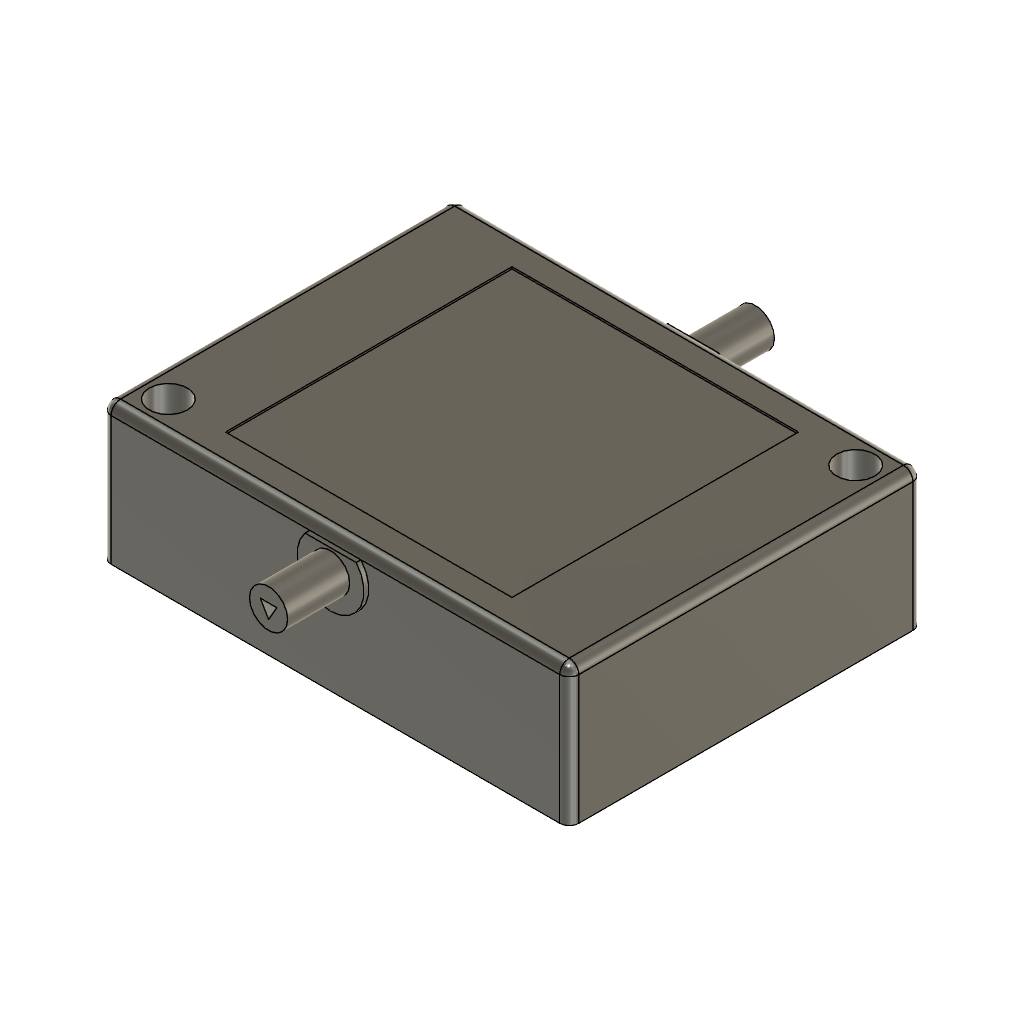
CompletedLook (Autodesk Fusion 360 archive; units mm, degrees)
design "CasePart3"
part number: 2026-10-03-21-02-19-954
Autodesk Fusion 360 part; units mm, degrees
sketch "Szkic1" plane through (0, 0, 0) normal (0, 0, 1) x (1, 0, 0)
  line L0 (0, 0) -> (49, 0)
  line L1 (49, 0) -> (49, 37)
  line L2 (49, 37) -> (0, 37)
  line L3 (0, 37) -> (0, 0)
  constraint horizontal L0
  constraint vertical L1
  constraint horizontal L2
  constraint vertical L3
  constraint coincident L0.start L3.end
extrude "Wyciągnięcie proste1" add sketch "Szkic1" along normal blind 2
sketch "Szkic2" plane through (0, 0, 0) normal (0, 0, -1) x (1, 0, 0)
  line L0 (0, 0) -> (0, -37)
  line L1 (0, -37) -> (49, -37)
  line L2 (49, -37) -> (49, 0)
  line L3 (49, 0) -> (0, 0)
  line L4 (0, 0) -> (49, 0)
  line L5 (49, 0) -> (49, -37)
  line L6 (49, -37) -> (42, -37)
  line L7 (0, -37) -> (0, 0)
  line L8 (7, -2) -> (47, -2)
  line L9 (47, -2) -> (47, -30)
  line L10 (42, -35) -> (2, -35)
  line L11 (2, -35) -> (14, -35)
  line L12 (12.5, -15) -> (2, -15)
  line L13 (2, -15) -> (2, -35)
  line L14 (47, -2) -> (35, -2)
  line L15 (36.5, -22) -> (47, -22)
  line L16 (47, -22) -> (47, -2)
  line L17 (2, -15) -> (12.5, -15)
  line L18 (13, -35) -> (2, -35)
  line L19 (2, -35) -> (2, -15)
  line L20 (47, -2) -> (36, -2)
  line L21 (36.5, -22) -> (47, -22)
  line L22 (47, -22) -> (47, -2)
  line L23 (12.5, -15) -> (12.5, -26.5)
  line L24 (36.5, -2) -> (36.5, -22)
  line L25 (0, 0) -> (7, 0)
  line L26 (7, 0) -> (7, -7)
  line L27 (7, -7) -> (0, -7)
  line L28 (0, -7) -> (0, 0)
  line L29 (2, -35) -> (2, -7)
  line L30 (49, -37) -> (42, -37)
  line L31 (42, -37) -> (42, -30)
  line L32 (42, -30) -> (49, -30)
  line L33 (49, -30) -> (49, -37)
  line L34 (19.5, -28.5) -> (19.5, -28.5)
  line L35 (19.5, -30.5) -> (19.5, -30.5)
  line L36 (12.5, -26.5) -> (12.5, -28.5)
  line L37 (12.5, -28.5) -> (12.5, -30.5)
  line L38 (12.5, -30.5) -> (19.5, -30.5)
  line L39 (29.5, -30.5) -> (35, -30.5)
  line L40 (29.5, -30.5) -> (37, -30.5)
  line L41 (2, -35) -> (21, -35)
  line L42 (49, -37) -> (42, -37)
  line L43 (19.5, -30.5) -> (19.5, -35)
  line L44 (37, -30.5) -> (38, -30.5)
  line L45 (38, -30.5) -> (38, -35)
  line L46 (29.5, -35) -> (29.5, -30.5)
  line L47 (19.5, -5.5) -> (36.5, -5.5)
  line L48 (19.5, -5.5) -> (12.5, -5.5)
  line L49 (12.5, -2) -> (13.5, -2)
  line L50 (13.5, -5.5) -> (17, -5.5)
  line L51 (18, -5.5) -> (21.5, -5.5)
  line L52 (22.5, -5.5) -> (26, -5.5)
  line L53 (27, -5.5) -> (30.5, -5.5)
  line L54 (27, -5.5) -> (30.5, -5.5)
  line L55 (31.5, -5.5) -> (35, -5.5)
  line L56 (13, -5.5) -> (12.5, -5.5)
  line L57 (30, -5.5) -> (24.5, -5.5)
  line L58 (31.5, -2) -> (31.5, -4.5)
  line L59 (30.5, -2) -> (30.5, -4.5)
  line L60 (25.5, -2) -> (25.5, -4.5)
  line L61 (24.5, -2) -> (24.5, -4.5)
  line L62 (19.5, -2) -> (19.5, -4.5)
  line L63 (18.5, -2) -> (18.5, -4.5)
  line L64 (12.5, -2) -> (12.5, -5.5)
  line L65 (13.5, -2) -> (13.5, -4.5)
  line L66 (13.5, -2) -> (15, -2)
  line L67 (13.5, -2) -> (16, -2)
  line L68 (16, -2) -> (15.5, -2)
  line L69 (16, -2) -> (16.5, -2)
  line L70 (16.5, -2) -> (16.5, -4.5)
  line L71 (15.5, -4.5) -> (15.5, -2)
  line L72 (19.5, -2) -> (21.5, -2)
  line L73 (21.5, -4.5) -> (21.5, -2)
  line L74 (22.5, -2) -> (22.5, -4.5)
  line L75 (25.5, -2) -> (27.5, -2)
  line L76 (27.5, -4.5) -> (27.5, -2)
  line L77 (28.5, -4.5) -> (28.5, -2)
  line L78 (31.5, -2) -> (33.5, -2)
  line L79 (33.5, -2) -> (33.5, -4.5)
  line L80 (34.5, -4.5) -> (34.5, -2)
  line L81 (13.5, -4.5) -> (15.5, -4.5)
  line L82 (16.5, -4.5) -> (18.5, -4.5)
  line L83 (19.5, -4.5) -> (21.5, -4.5)
  line L84 (22.5, -4.5) -> (24.5, -4.5)
  line L85 (25.5, -4.5) -> (27.5, -4.5)
  line L86 (28.5, -4.5) -> (30.5, -4.5)
  line L87 (31.5, -4.5) -> (33.5, -4.5)
  line L88 (34.5, -4.5) -> (36.5, -4.5)
  constraint horizontal L4
  constraint vertical L5
  constraint horizontal L6
  constraint vertical L7
  constraint coincident L1.end L2.start
  constraint coincident L0.start L3.end
  constraint horizontal L8
  constraint vertical L9
  constraint horizontal L10
  constraint vertical L29
  constraint horizontal L11
  constraint horizontal L12
  constraint vertical L13
  constraint horizontal L14
  constraint horizontal L15
  constraint vertical L16
  constraint horizontal L17
  constraint horizontal L18
  constraint vertical L19
  constraint coincident L11 L18.start
  constraint horizontal L20
  constraint horizontal L21
  constraint vertical L22
  constraint perpendicular L11 L23
  constraint coincident L14 L24.start
  constraint perpendicular L15 L24
  constraint horizontal L25
  constraint vertical L26
  constraint horizontal L27
  constraint vertical L28
  constraint coincident L27 L29.end
  constraint coincident L26 L8.start
  constraint horizontal L30
  constraint vertical L31
  constraint horizontal L32
  constraint vertical L33
  constraint coincident L31 L10.start
  constraint coincident L32 L9.end
  constraint horizontal L38
  constraint collinear L38 L39
  constraint coincident L10 L41.end
  constraint coincident L41 L43.end
  constraint coincident L10 L45.end
  constraint perpendicular L10 L45
  constraint coincident L10 L46.start
  constraint coincident L24 L47.end
  constraint perpendicular L24 L47
  constraint coincident L8 L49.start
  constraint coincident L8 L49.end
  constraint coincident L48 L50.start
  constraint coincident L48 L50.end
  constraint coincident L48 L51.start
  constraint coincident L47 L51.end
  constraint coincident L47 L52.start
  constraint coincident L47 L52.end
  constraint coincident L47 L53.start
  constraint coincident L47 L53.end
  constraint coincident L47 L55.start
  constraint coincident L47 L55.end
  constraint coincident L48 L56.start
  constraint coincident L53 L57.start
  constraint coincident L52 L57.end
  constraint coincident L8 L58.start
  constraint perpendicular L55 L58
  constraint coincident L8 L59.start
  constraint perpendicular L54 L59
  constraint coincident L8 L60.start
  constraint coincident L8 L61.start
  constraint perpendicular L52 L61
  constraint coincident L8 L62.start
  constraint perpendicular L8 L62
  constraint coincident L8 L63.start
  constraint perpendicular L48 L64
  constraint perpendicular L48 L65
  constraint perpendicular L63 L82
  constraint perpendicular L61 L84
  constraint perpendicular L59 L86
  constraint coincident L24 L88.end
  constraint perpendicular L24 L88
  constraint coincident L8 L66.end
  constraint perpendicular L63 L66
  constraint coincident L8 L67.end
  constraint coincident L67 L68.end
  constraint coincident L8 L69.end
  constraint perpendicular L70 L82
  constraint perpendicular L67 L71
  constraint coincident L8 L72.end
  constraint perpendicular L72 L73
  constraint coincident L8 L74.start
  constraint perpendicular L74 L84
  constraint coincident L8 L75.end
  constraint perpendicular L60 L75
  constraint perpendicular L75 L76
  constraint coincident L8 L77.end
  constraint perpendicular L8 L77
  constraint coincident L8 L78.end
  constraint perpendicular L79 L87
  constraint coincident L8 L80.end
  constraint perpendicular L8 L80
  constraint collinear L81 L82
  constraint collinear L83 L84
  constraint collinear L85 L86
  constraint collinear L87 L88
extrude "Wyciągnięcie proste2" add sketch "Szkic2" along normal blind 12.5 contours L0 L3 L4 L7 L25 L26 L27 L28 | L0 L1 L7 L10 L11 L13 L18 L19 L27 L29 L31 L41 | L2 L3 L4 L5 L8 L9 L14 L16 L20 L22 L26 L32 L49 L66 L67 L68 L69 L72 L75 L78 | L1 L2 L5 L6 L30 L31 L32 L33 L42 | L10 L11 L12 L13 L17 L18 L19 L23 L29 L36 L37 L38 L41 L43 | L8 L24 L47 L48 L49 L50 L51 L52 L53 L54 L55 L56 L57 L58 L59 L60 L61 L62 L63 L64 L65 L67 L68 L69 L70 L71 L73 L74 L76 L77 L79 L80 L81 L82 L83 L84 L85 L86 L87 L88 | L10 L39 L40 L44 L45 L46 | L8 L9 L14 L15 L16 L20 L21 L22 L24
sketch "Szkic8" plane through (0, 0, 2) normal (0, 0, 1) x (-1, 0, 0)
  line L0 (0, -37) -> (0, 0)
  line L1 (0, 0) -> (-49, 0)
  line L2 (-49, 0) -> (-49, -37)
  line L3 (-49, -37) -> (0, -37)
  line L4 (-49, -37) -> (-45.5, -37)
  line L5 (-45.5, -37) -> (-45.5, -33.5)
  line L6 (0, 0) -> (-3.5, 0)
  line L7 (-3.5, 0) -> (-3.5, -3.5)
  circle A0 centre (-3.5, -3.5) radius 2
  circle A1 centre (-45.5, -33.5) radius 2
  dimension "d17" = 4
  dimension "d18" = 4
  constraint coincident L2.end L3.start
  constraint coincident L3 L4.end
  constraint perpendicular L4 L5
  constraint coincident L0.end L1.start
  constraint coincident L1 L6.end
  constraint perpendicular L1 L7
  constraint coincident L7.end A0.centre
  constraint coincident L5.end A1.centre
  measures "d17" diameter of A0
  measures "d18" diameter of A1
extrude "Wyciągnięcie proste6" cut sketch "Szkic8" against normal blind 14 contours A0 | A1
sketch "Szkic13" plane through (0, 37, 0) normal (0, 1, 0) x (-1, 0, 0)
  line L0 (0, 2) -> (-49, 2)
  line L1 (-49, -12.5) -> (0, -12.5)
  line L2 (0, -12.5) -> (-24.5, -12.5)
  line L3 (-24.5, -12.5) -> (-24.5, -9.5)
  line L4 (-24.5, -12.5) -> (-24.5, -9.5)
  line L5 (-24.5, -9.5) -> (-28.75, -9.5)
  line L6 (-28.75, -9.5) -> (-24.5, -9.5)
  line L7 (-24.5, -9.5) -> (-20, -9.5)
  line L8 (-49, -12.5) -> (-24.5, -12.5)
  line L9 (-24.5, -9.5) -> (-29.5, -9.5)
  line L10 (-29.5, -9.5) -> (-29.5, -4.5)
  line L11 (-19.5, -9.5) -> (-19.5, -4.5)
  line L12 (-19.5, -4.5) -> (-20.25, -4.5)
  line L13 (-29.5, -4.5) -> (-20.25, -4.5)
  line L14 (-20, -9.5) -> (-19.5, -9.5)
  line L15 (0, -12.5) -> (0, 2)
  line L16 (-49, 2) -> (-49, -12.5)
  constraint midpoint L1 L2.end
  constraint perpendicular L1 L3
  constraint perpendicular L4 L5
  constraint perpendicular L4 L7
  constraint perpendicular L4 L9
  constraint perpendicular L5 L10
  constraint perpendicular L10 L13
  constraint perpendicular L11 L14
extrude "Wyciągnięcie proste11" cut sketch "Szkic13" against normal blind 2 contours L5 L6 L7 L9 L10 L11 L12 L13 L14
sketch "Szkic15" plane through (0, 0, -12) normal (0, 0, 1) x (-1, 0, 0)
  circle A0 centre (-3.5, -3.5) radius 2
  circle A1 centre (-3.5, -3.5) radius 1.5
  circle A2 centre (-45.5, -33.5) radius 1.5
  dimension "d39" = 3
  dimension "d40" = 3
  constraint concentric A0 A1
  measures "d39" diameter of A1
  measures "d40" diameter of A2
extrude "Wyciągnięcie proste13" cut sketch "Szkic15" against normal blind 1 contours A1 | A2
sketch "Szkic16" plane through (0, 37, 0) normal (0, 1, 0) x (-1, 0, 0)
  line L0 (-19.5, -4.5) -> (-19.5, -9.5)
  line L1 (-19.5, -9.5) -> (-29.5, -9.5)
  line L2 (-29.5, -9.5) -> (-29.5, -4.5)
  line L3 (-29.5, -4.5) -> (-19.5, -4.5)
  line L4 (0, 2) -> (-49, 2)
  line L5 (-49, -12.5) -> (0, -12.5)
  line L6 (-49, 2) -> (-24.5, 2)
  line L7 (-24.5, 2) -> (-24.5, -1.25)
  circle A0 centre (-24.5, -1.25) radius 2
  line L8 (0, -12.5) -> (0, 2)
  line L9 (-49, 2) -> (-49, -12.5)
  dimension "d47" = 24.5
  dimension "d48" = 3.25
  dimension "d49" = 4
  constraint perpendicular L3 L7
  constraint coincident L7.end A0.centre
  measures "d47" distance of L4.end L6.end
  measures "d48" distance of L6.end L7.end
  measures "d49" diameter of A0
extrude "Wyciągnięcie proste14" add sketch "Szkic16" along normal blind 7 contours A0
sketch "Szkic17" plane through (0, 0, 0) normal (0, -1, 0) x (1, 0, 0)
  line L0 (49, 2) -> (0, 2)
  line L1 (0, -12.5) -> (49, -12.5)
  line L2 (0, 2) -> (24.5, 2)
  line L3 (24.5, 2) -> (24.5, -1.25)
  circle A0 centre (24.5, -1.25) radius 2
  line L4 (49, -12.5) -> (49, 2)
  line L5 (0, 2) -> (0, -12.5)
  dimension "d52" = 24.5
  dimension "d53" = 3.25
  dimension "d54" = 4
  constraint perpendicular L2 L3
  constraint coincident L3.end A0.centre
  measures "d52" distance of L0.end L2.end
  measures "d53" distance of L2.end L3.end
  measures "d54" diameter of A0
extrude "Wyciągnięcie proste15" add sketch "Szkic17" along normal blind 7 contours A0
sketch "Szkic11" plane through (0, 0, 2) normal (0, 0, 1) x (-1, 0, 0)
  circle A0 centre (-3.5, -3.5) radius 2
  circle A1 centre (-45.5, -33.5) radius 2
  line L0 (0, -37) -> (0, 0)
  line L1 (0, 0) -> (-49, 0)
  line L2 (-49, 0) -> (-49, -37)
  line L3 (-49, -37) -> (0, -37)
  line L4 (0, 0) -> (-24.5, 0)
  line L5 (-24.5, 0) -> (-24.5, -3.5)
  line L6 (-9.5, -33) -> (-9.5, -33)
  line L7 (-10, -33) -> (-10, -33)
  line L8 (-9.5, -33) -> (-9.5, -33.5)
  line L9 (-9.5, -33.5) -> (-39.5, -33.5)
  line L10 (-39.5, -33.5) -> (-39.5, -3.5)
  line L11 (-39.5, -3.5) -> (-9.5, -3.5)
  line L12 (-9.5, -3.5) -> (-9.5, -33.5)
  constraint coincident L0.end L1.start
  constraint midpoint L1 L4.end
  constraint perpendicular L4 L5
  constraint horizontal L9
  constraint vertical L10
  constraint horizontal L11
  constraint vertical L12
  constraint coincident L11 L5.end
extrude "Wyciągnięcie proste9" cut sketch "Szkic11" against normal blind 0.2 contours L8 L9 L10 L11 L12
sketch "Szkic18" plane through (0, 44, 0) normal (0, 1, 0) x (-1, 0, 0)
  circle A0 centre (-24.5, -1.25) radius 2
  circle A1 centre (-24.5, -1.25) radius 2
  circle A2 centre (-24.5, -1.25) radius 1
  line L0 (-24.5, -1.25) -> (-24.5, -2.25)
  line L1 (-24.5, -2.25) -> (-25.3652, -0.7485)
  line L2 (-24.5, -2.25) -> (-23.6348, -0.7485)
  line L3 (-25.3652, -0.7485) -> (-23.6348, -0.7485)
  dimension "d57" = 2
  constraint concentric A0 A1
  constraint concentric A1 A2
  constraint coincident A0.centre A1.centre
  constraint coincident A2 L0.end
  constraint vertical L0
  constraint coincident A2 L1.end
  constraint coincident A2 L2.end
  constraint horizontal L3
  measures "d57" diameter of A2
extrude "Wyciągnięcie proste16" cut sketch "Szkic18" against normal blind 3 contours L1 L2 L3
sketch "Szkic19" plane through (0, -7, 0) normal (0, -1, 0) x (1, 0, 0)
  circle A0 centre (24.5, -1.25) radius 2
  circle A1 centre (24.5, -1.25) radius 2
  circle A2 centre (24.5, -1.25) radius 1
  line L0 (24.5, -1.25) -> (24.5, -2.25)
  line L1 (24.5, -2.25) -> (25.366, -0.7499)
  line L2 (24.5, -2.25) -> (23.634, -0.7499)
  line L3 (23.634, -0.7499) -> (25.366, -0.7499)
  dimension "d60" = 2
  constraint concentric A0 A1
  constraint concentric A1 A2
  constraint coincident A0.centre A1.centre
  constraint coincident A2 L0.end
  constraint vertical L0
  constraint coincident A2 L1.end
  constraint coincident A2 L2.end
  constraint horizontal L3
  measures "d60" diameter of A2
extrude "Wyciągnięcie proste17" cut sketch "Szkic19" against normal blind 3 contours L1 L2 L3
fillet "Zaokrąglenie2" radius 1 8 edges at (0, 37, -5.25) (0, 0, -5.25) (0, 18.5, 2) (24.5, 37, 2) (49, 37, -5.25) (49, 18.5, 2) (24.5, 0, 2) (49, 0, -5.25)
sketch "Szkic20" plane through (0, 0, 0) normal (0, -1, 0) x (1, 0, 0)
  line L0 (48, -12.5) -> (48, 1)
  line L1 (48, 1) -> (1, 1)
  line L2 (1, 1) -> (1, -12.5)
  line L3 (1, -12.5) -> (48, -12.5)
  circle A0 centre (24.5, -1.25) radius 2
  circle A1 centre (24.5, -1.25) radius 3.5
  dimension "d66" = 7
  measures "d66" diameter of A1
extrude "Wyciągnięcie proste18" add sketch "Szkic20" along normal blind 0.5 contours L1 A1 picked at (22.0612, 0.4859)
sketch "Szkic21" plane through (0, 37, 0) normal (0, 1, 0) x (-1, 0, 0)
  line L0 (-48, 1) -> (-48, -12.5)
  line L1 (-48, -12.5) -> (-1, -12.5)
  line L2 (-1, -12.5) -> (-1, 1)
  line L3 (-1, 1) -> (-48, 1)
  circle A0 centre (-24.5, -1.25) radius 2
  line L4 (-19.5, -4.5) -> (-19.5, -9.5)
  line L5 (-19.5, -9.5) -> (-29.5, -9.5)
  line L6 (-29.5, -9.5) -> (-29.5, -4.5)
  line L7 (-29.5, -4.5) -> (-19.5, -4.5)
  circle A1 centre (-24.5, -1.25) radius 3.5
  dimension "d69" = 7
  constraint concentric A0 A1
  measures "d69" diameter of A1
extrude "Wyciągnięcie proste19" add sketch "Szkic21" along normal blind 0.5 contours L3 L7 A1
equation "d47 = ( 49.000 / 2 ) * 1 mm"
equation "d48 = ( 6.500 / 2 ) * 1 mm"
equation "d52 = ( 49.000 / 2 ) * 1 mm"

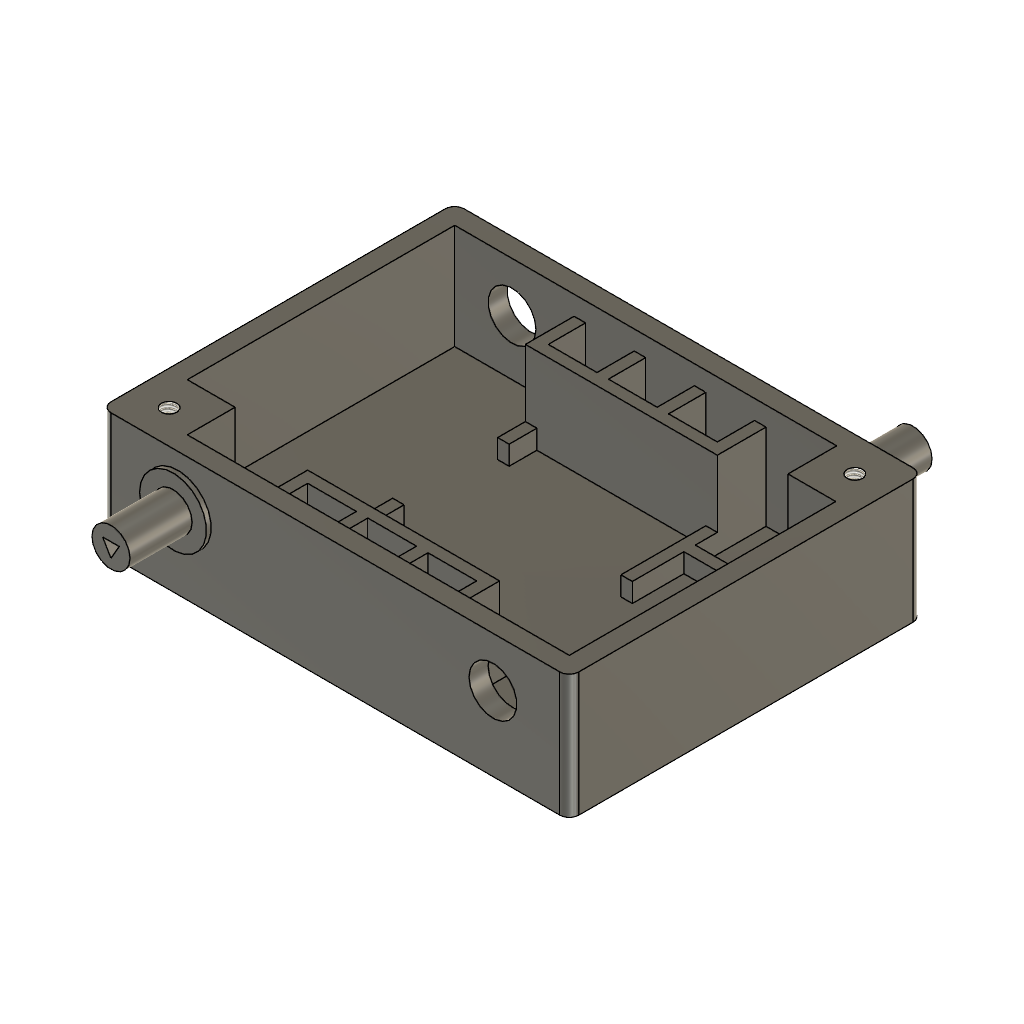
design "CasePart1"
part number: 2026-10-03-18-17-18-057
Autodesk Fusion 360 part; units mm, degrees
sketch "Szkic1" plane through (0, 0, 0) normal (0, 0, 1) x (1, 0, 0)
  line L0 (0, 0) -> (49, 0)
  line L1 (49, 0) -> (49, 37)
  line L2 (49, 37) -> (0, 37)
  line L3 (0, 37) -> (0, 0)
  constraint horizontal L0
  constraint vertical L1
  constraint horizontal L2
  constraint vertical L3
  constraint coincident L0.start L3.end
extrude "Wyciągnięcie proste1" add sketch "Szkic1" along normal blind 2
sketch "Szkic2" plane through (0, 0, 2) normal (0, 0, 1) x (-1, 0, 0)
  line L0 (0, -37) -> (0, 0)
  line L1 (0, 0) -> (-49, 0)
  line L2 (-49, 0) -> (-49, -37)
  line L3 (-49, -37) -> (0, -37)
  line L4 (0, -37) -> (-2, -37)
  line L5 (-2, 0) -> (0, 0)
  line L6 (0, 0) -> (0, -37)
  line L7 (-14.5, -2) -> (-47, -2)
  line L8 (-49, -2) -> (-49, 0)
  line L9 (-49, 0) -> (-2, 0)
  line L10 (-49, -2) -> (-49, -37)
  line L11 (-49, -37) -> (-47, -37)
  line L12 (-47, -29.9) -> (-47, -2)
  line L13 (-2, -37) -> (-47, -37)
  line L14 (-34.5, -35) -> (-2, -35)
  line L15 (-2, -35) -> (-2, -7.1)
  line L16 (-47, -29.9) -> (-42, -29.9)
  line L17 (-34.5, -29.9) -> (-34.5, -30)
  line L18 (-7, -2) -> (-7, -7)
  line L19 (-7, -7) -> (-2, -7)
  line L20 (-2, -7) -> (-2, -7.1)
  line L21 (-14.5, -2) -> (-7, -2)
  line L22 (-42, -35) -> (-42, -29.9)
  line L23 (-42, -35) -> (-34.5, -35)
  constraint horizontal L4
  constraint vertical L15
  constraint horizontal L5
  constraint vertical L6
  constraint coincident L1 L5.start
  constraint coincident L0.start L3.end
  constraint horizontal L7
  constraint vertical L8
  constraint horizontal L9
  constraint coincident L1.end L2.start
  constraint vertical L10
  constraint horizontal L11
  constraint vertical L12
  constraint coincident L2.end L3.start
  constraint horizontal L13
  constraint horizontal L14
  constraint horizontal L16
  constraint vertical L17
  constraint perpendicular L18 L19
  constraint parallel L1 L21
  constraint perpendicular L16 L22
extrude "Wyciągnięcie proste2" add sketch "Szkic2" along normal blind 11
sketch "Szkic3" plane through (0, 0, 2) normal (0, 0, 1) x (-1, 0, 0)
  line L0 (-2, -35) -> (-2, -7.1)
  line L1 (-14.5, -2) -> (-47, -2)
  line L2 (-47, -2) -> (-47, -29.9)
  line L3 (-42, -35) -> (-2, -35)
  line L4 (-10, -10.6) -> (-2, -10.6)
  line L5 (-14.5, -27) -> (-14.5, -35)
  line L6 (-10, -10.6) -> (-14.5, -10.6)
  line L7 (-14.5, -10.6) -> (-14.5, -16)
  line L8 (-14.5, -9.4) -> (-14.5, -2)
  line L9 (-13.8092, -9.4) -> (-14.5, -9.4)
  line L10 (-13.8092, -9.4) -> (-2, -9.4)
  line L11 (-15.7, -35) -> (-15.7, -31.1)
  line L12 (-20, -31.1) -> (-15.7, -31.1)
  line L13 (-20, -29.9) -> (-15.7, -29.9)
  line L14 (-15.7, -27) -> (-15.7, -29.9)
  line L15 (-15.7, -31.1) -> (-15.7, -35)
  line L16 (-20, -29.9) -> (-33.4, -29.9)
  line L17 (-34.5, -29.9) -> (-42, -29.9)
  line L18 (-34.6, -33.7358) -> (-34.6, -35)
  line L19 (-34.6, -35) -> (-33.4, -35)
  line L20 (-33.4, -35) -> (-33.4, -31.1)
  line L21 (-34.6, -33.7358) -> (-34.6, -31.1)
  line L22 (-34.6, -31.1) -> (-34.6, -29.9)
  line L23 (-47, -27.6) -> (-47, -26.4)
  line L24 (-47, -29.9) -> (-47, -27.6)
  line L25 (-47, -27.6) -> (-47, -26.4)
  line L26 (-43.1782, -26.4) -> (-47, -26.4)
  line L27 (-47, -27.6) -> (-42.2525, -27.6)
  line L28 (-42.2525, -26.4) -> (-43.1782, -26.4)
  line L29 (-33.4, -2) -> (-34.6, -2)
  line L30 (-34.6, -27.6) -> (-42.2525, -27.6)
  line L31 (-42.2525, -26.4) -> (-34.6, -26.4)
  line L32 (-20, -31.1) -> (-33.4, -31.1)
  line L33 (-34.6, -30.1881) -> (-34.6, -27.6)
  line L34 (-18.5, -5.9) -> (-15.7, -5.9)
  line L35 (-20, -7.1) -> (-15.7, -7.1)
  line L36 (-20, -7.1) -> (-33.4, -7.1)
  line L37 (-18.5, -5.9) -> (-33.4, -5.9)
  line L38 (-15.7, -16) -> (-15.7, -7.1)
  line L39 (-15.7, -5.9) -> (-15.7, -2)
  line L40 (-33.4, -5.9) -> (-33.4, -2)
  line L41 (-14.5, -2) -> (-15.7, -2)
  line L42 (-33.4, -21) -> (-34.6, -21)
  line L43 (-33.4, -10) -> (-34.6, -10)
  line L44 (-33.4, -2) -> (-33.4, -5.9)
  line L45 (-33.4, -7.1) -> (-33.4, -10)
  line L46 (-33.4, -35) -> (-33.4, -31.1)
  line L47 (-33.4, -29.9) -> (-33.4, -21)
  line L48 (-15.7, -16) -> (-14.5, -16)
  line L49 (-15.7, -2) -> (-15.7, -5.9)
  line L50 (-15.7, -7.1) -> (-15.7, -16)
  line L51 (-14.5, -35) -> (-14.5, -27)
  line L52 (-14.5, -35) -> (-14.5, -27)
  line L53 (-15.7, -27) -> (-14.5, -27)
  line L54 (-34.6, -26.4) -> (-34.6, -21)
  line L55 (-34.6, -10) -> (-34.6, -2)
  line L56 (-33.4, -29.9) -> (-33.4, -21)
  line L57 (-33.4, -10) -> (-33.4, -7.1)
  line L58 (-47, -29.9) -> (-42, -29.9)
  line L59 (-42, -29.9) -> (-42, -35)
  line L60 (-2, -7.1) -> (-2, -7)
  line L61 (-2, -7) -> (-7, -7)
  line L62 (-7, -7) -> (-7, -2)
  line L63 (-7, -2) -> (-14.5, -2)
  line L64 (-15.7, -29.9) -> (-14.5, -29.9)
  line L65 (-34.6, -29.9) -> (-33.4, -29.9)
  line L66 (-15.7, -7.1) -> (-14.5, -7.1)
  line L67 (-33.4, -7.1) -> (-34.6, -7.1)
  constraint coincident L0 L4.end
  constraint perpendicular L0 L4
  constraint coincident L3 L5.end
  constraint perpendicular L3 L5
  constraint coincident L3 L11.start
  constraint perpendicular L3 L15
  constraint coincident L1 L39.end
  constraint perpendicular L1 L39
  constraint coincident L1 L8.end
  constraint perpendicular L1 L8
  constraint perpendicular L8 L9
  constraint coincident L0 L10.end
  constraint perpendicular L0 L10
  constraint perpendicular L11 L12
  constraint perpendicular L13 L14
  constraint collinear L14 L15
  constraint coincident L3 L18.end
  constraint perpendicular L3 L18
  constraint coincident L3 L19.end
  constraint perpendicular L20 L32
  constraint perpendicular L16 L22
  constraint coincident L2 L23.start
  constraint coincident L2 L23.end
  constraint coincident L2.end L24.start
  constraint perpendicular L25 L26
  constraint perpendicular L23 L27
  constraint coincident L1 L29.start
  constraint perpendicular L1 L40
  constraint coincident L22 L33.start
  constraint coincident L1 L29.end
  constraint perpendicular L1 L55
  constraint perpendicular L31 L54
  constraint collinear L33 L54
  constraint perpendicular L34 L39
  constraint perpendicular L35 L38
  constraint perpendicular L36 L57
  constraint perpendicular L37 L40
  constraint collinear L38 L39
  constraint collinear L40 L57
  constraint perpendicular L3 L46
  constraint perpendicular L42 L56
  constraint perpendicular L43 L55
  constraint collinear L44 L45
  constraint collinear L46 L47
  constraint perpendicular L7 L48
  constraint collinear L49 L50
  constraint perpendicular L5 L53
  constraint collinear L54 L55
  constraint collinear L56 L57
  constraint coincident L51 L64.end
  constraint perpendicular L51 L64
  constraint perpendicular L56 L65
  constraint coincident L8 L66.end
  constraint perpendicular L8 L66
  constraint coincident L55 L67.end
  constraint perpendicular L55 L67
extrude "Wyciągnięcie proste3" add sketch "Szkic3" along normal blind 2 contours L0 L4 L6 L7 L8 L9 L10 L38 L48 L50 L66 | L3 L5 L11 L12 L13 L15 L16 L17 L18 L19 L20 L21 L22 L32 L33 L46 L51 L52 L64 L65 | L5 L14 L51 L52 L53 L64 | L1 L8 L29 L34 L35 L36 L37 L39 L40 L41 L44 L49 L55 L66 L67 | L2 L17 L23 L25 L26 L27 L28 L30 L31 L33 L42 L47 L54 L56 L65 | L43 L45 L55 L57 L67
sketch "Szkic4" plane through (0, 0, 4) normal (0, 0, 1) x (-1, 0, 0)
  line L0 (-15.7, -29.9) -> (-33.4, -29.9)
  line L1 (-33.4, -29.9) -> (-33.4, -21)
  line L2 (-33.4, -21) -> (-34.6, -21)
  line L3 (-34.6, -21) -> (-34.6, -26.4)
  line L4 (-34.6, -26.4) -> (-47, -26.4)
  line L5 (-47, -26.4) -> (-47, -27.6)
  line L6 (-47, -27.6) -> (-34.6, -27.6)
  line L7 (-34.6, -27.6) -> (-34.6, -35)
  line L8 (-34.6, -35) -> (-33.4, -35)
  line L9 (-33.4, -35) -> (-33.4, -31.1)
  line L10 (-33.4, -31.1) -> (-15.7, -31.1)
  line L11 (-15.7, -31.1) -> (-15.7, -35)
  line L12 (-15.7, -35) -> (-14.5, -35)
  line L13 (-14.5, -35) -> (-14.5, -27)
  line L14 (-14.5, -27) -> (-15.7, -27)
  line L15 (-15.7, -27) -> (-15.7, -29.9)
  line L16 (-14.5, -35) -> (-15.7, -35)
  line L17 (-15.7, -35) -> (-15.7, -31.1)
  line L18 (-15.7, -29.9) -> (-14.5, -29.9)
  line L19 (-14.5, -29.9) -> (-14.5, -35)
  line L20 (-15.7, -29.9) -> (-34.6, -29.9)
  line L21 (-34.6, -29.9) -> (-34.6, -31.1)
  line L22 (-33.4, -31.1) -> (-15.7, -31.1)
  line L23 (-33.4, -31.1) -> (-33.4, -35)
  line L24 (-33.4, -35) -> (-34.6, -35)
  line L25 (-34.6, -35) -> (-34.6, -31.1)
  line L26 (-15.7, -31.1) -> (-20, -31.1)
  line L27 (-33.4, -31.1) -> (-29, -31.1)
  line L28 (-33.4, -31.1) -> (-28.3, -31.1)
  line L29 (-28.3, -31.1) -> (-28.3, -35)
  line L30 (-28.3, -35) -> (-27.1, -35)
  line L31 (-27.1, -35) -> (-27.1, -31.1)
  line L32 (-27.1, -31.1) -> (-22, -31.1)
  line L33 (-22, -31.1) -> (-22, -35)
  line L34 (-22, -35) -> (-20.8, -35)
  line L35 (-20.8, -35) -> (-20.8, -31.1)
  dimension "d67" = 5.1
  dimension "d68" = 1.2
  dimension "d69" = 5.1
  dimension "d70" = 1.2
  constraint horizontal L16
  constraint vertical L17
  constraint horizontal L18
  constraint vertical L19
  constraint coincident L0.start L15.end
  constraint coincident L12.end L13.start
  constraint horizontal L20
  constraint vertical L21
  constraint horizontal L22
  constraint coincident L7 L21.end
  constraint vertical L23
  constraint horizontal L24
  constraint vertical L25
  constraint coincident L8.end L9.start
  constraint coincident L22 L26.end
  constraint coincident L9.end L10.start
  constraint coincident L22 L27.end
  constraint perpendicular L11 L28
  constraint perpendicular L28 L29
  constraint perpendicular L29 L30
  constraint coincident L22 L31.end
  constraint perpendicular L22 L31
  constraint perpendicular L31 L32
  constraint perpendicular L10 L33
  constraint perpendicular L33 L34
  constraint coincident L22 L35.end
  constraint perpendicular L22 L35
  measures "d67" distance of L9.end L28.end
  measures "d68" distance of L29.end L30.end
  measures "d69" distance of L31.end L32.end
  measures "d70" distance of L33.end L34.end
extrude "Wyciągnięcie proste4" add sketch "Szkic4" along normal blind 7 contours L0 L7 L8 L9 L10 L11 L12 L13 L16 L17 L18 L19 L20 L21 L22 L23 L24 L25 L26 L27 L28 L32 | L10 L22 L33 L34 L35 | L10 L22 L29 L30 L31
sketch "Szkic5" plane through (0, 0, 4) normal (0, 0, 1) x (-1, 0, 0)
  line L0 (-34.6, -10) -> (-33.4, -10)
  line L1 (-33.4, -10) -> (-33.4, -7.1)
  line L2 (-33.4, -7.1) -> (-15.7, -7.1)
  line L3 (-15.7, -7.1) -> (-15.7, -16)
  line L4 (-15.7, -16) -> (-14.5, -16)
  line L5 (-14.5, -16) -> (-14.5, -10.6)
  line L6 (-14.5, -10.6) -> (-2, -10.6)
  line L7 (-2, -10.6) -> (-2, -9.4)
  line L8 (-2, -9.4) -> (-14.5, -9.4)
  line L9 (-14.5, -9.4) -> (-14.5, -2)
  line L10 (-14.5, -2) -> (-15.7, -2)
  line L11 (-15.7, -2) -> (-15.7, -5.9)
  line L12 (-15.7, -5.9) -> (-33.4, -5.9)
  line L13 (-33.4, -5.9) -> (-33.4, -2)
  line L14 (-33.4, -2) -> (-34.6, -2)
  line L15 (-34.6, -2) -> (-34.6, -10)
  line L16 (-34.6, -2) -> (-33.4, -2)
  line L17 (-33.4, -2) -> (-33.4, -5.9)
  line L18 (-33.4, -7.1) -> (-34.6, -7.1)
  line L19 (-34.6, -7.1) -> (-34.6, -2)
  line L20 (-33.4, -7.1) -> (-14.5, -7.1)
  line L21 (-14.5, -7.1) -> (-14.5, -5.9)
  line L22 (-15.7, -5.9) -> (-15.7, -2)
  line L23 (-15.7, -2) -> (-14.5, -2)
  line L24 (-14.5, -2) -> (-14.5, -5.9)
  line L25 (-33.4, -5.9) -> (-28.3, -5.9)
  line L26 (-28.3, -5.9) -> (-28.3, -2)
  line L27 (-28.3, -2) -> (-27.1, -2)
  line L28 (-27.1, -2) -> (-27.1, -5.9)
  line L29 (-27.1, -5.9) -> (-22, -5.9)
  line L30 (-22, -5.9) -> (-22, -2)
  line L31 (-22, -2) -> (-20.8, -2)
  line L32 (-20.8, -2) -> (-20.8, -5.9)
  line L33 (-33.4, -5.9) -> (-28.3, -5.9)
  line L34 (-27.1, -5.9) -> (-22, -5.9)
  line L35 (-20.8, -5.9) -> (-15.7, -5.9)
  line L36 (-33.4, -7.1) -> (-14.5, -7.1)
  dimension "d71" = 5.1
  dimension "d72" = 1.2
  dimension "d73" = 5.1
  dimension "d74" = 1.2
  constraint horizontal L16
  constraint vertical L17
  constraint horizontal L18
  constraint vertical L19
  constraint coincident L1.end L2.start
  constraint coincident L14.end L15.start
  constraint horizontal L20
  constraint vertical L21
  constraint coincident L9 L21.end
  constraint vertical L22
  constraint horizontal L23
  constraint vertical L24
  constraint coincident L10.end L11.start
  constraint coincident L12.end L13.start
  constraint perpendicular L22 L35
  constraint perpendicular L13 L25
  constraint perpendicular L12 L26
  constraint perpendicular L26 L27
  constraint coincident L12 L28.end
  constraint perpendicular L12 L28
  constraint perpendicular L28 L29
  constraint perpendicular L12 L30
  constraint perpendicular L30 L31
  constraint coincident L12 L32.end
  constraint perpendicular L12 L32
  constraint collinear L33 L34
  constraint collinear L34 L35
  measures "d71" distance of L12.end L25.end
  measures "d72" distance of L26.end L27.end
  measures "d73" distance of L28.end L29.end
  measures "d74" distance of L30.end L31.end
extrude "Wyciągnięcie proste5" add sketch "Szkic5" along normal blind 7 contours L2 L9 L10 L11 L12 L13 L14 L15 L16 L17 L18 L19 L20 L21 L22 L23 L24 L25 L29 L33 L34 L35 L36 | L12 L26 L27 L28 | L12 L30 L31 L32
sketch "Szkic12" plane through (0, 0, 0) normal (0, -1, 0) x (1, 0, 0)
  line L0 (0, 0) -> (49, 0)
  line L1 (49, 0) -> (49, 13)
  line L2 (49, 13) -> (0, 13)
  line L3 (0, 13) -> (0, 0)
  line L4 (0, 0) -> (8, 0)
  line L5 (8, 0) -> (8, 7.8)
  circle A0 centre (8, 7.8) radius 2
  dimension "d27" = 8
  dimension "d28" = 7.8
  dimension "d62" = 4
  constraint coincident L0.start L3.end
  constraint perpendicular L3 L4
  constraint perpendicular L4 L5
  constraint coincident L5.end A0.centre
  measures "d27" distance of L0.start L4.end
  measures "d28" distance of L4.end L5.end
  measures "d62" diameter of A0
extrude "Wyciągnięcie proste8" add sketch "Szkic12" along normal blind 7 contours A0
sketch "Szkic13" plane through (0, 0, 0) normal (0, -1, 0) x (1, 0, 0)
  line L0 (0, 0) -> (49, 0)
  line L1 (49, 0) -> (49, 13)
  line L2 (49, 13) -> (0, 13)
  line L3 (0, 13) -> (0, 0)
  line L4 (49, 0) -> (41, 0)
  line L5 (41, 0) -> (41, 7.8)
  circle A0 centre (41, 7.8) radius 2.5
  circle A1 centre (8, 7.8) radius 2
  dimension "d54" = 8
  dimension "d55" = 7.8
  dimension "d56" = 5
  constraint coincident L0.end L1.start
  constraint perpendicular L1 L4
  constraint perpendicular L0 L5
  constraint coincident L5.end A0.centre
  measures "d54" distance of L0.end L4.end
  measures "d55" distance of L4.end L5.end
  measures "d56" diameter of A0
extrude "Wyciągnięcie proste9" cut sketch "Szkic13" against normal blind 2 contours A0
sketch "Szkic14" plane through (0, 37, 0) normal (0, 1, 0) x (-1, 0, 0)
  line L0 (-49, 0) -> (0, 0)
  line L1 (0, 0) -> (0, 13)
  line L2 (0, 13) -> (-49, 13)
  line L3 (-49, 13) -> (-49, 0)
  line L4 (-49, 0) -> (-41, 0)
  line L5 (-41, 0) -> (-41, 7.8)
  circle A0 centre (-41, 7.8) radius 2
  dimension "d57" = 8
  dimension "d58" = 7.8
  dimension "d61" = 4
  constraint coincident L0.start L3.end
  constraint perpendicular L3 L4
  constraint perpendicular L0 L5
  measures "d57" distance of L0.start L4.end
  measures "d58" distance of L4.end L5.end
  measures "d61" diameter of A0
extrude "Wyciągnięcie proste10" add sketch "Szkic14" along normal blind 7 contours A0
sketch "Szkic15" plane through (0, 37, 0) normal (0, 1, 0) x (-1, 0, 0)
  line L0 (-49, 0) -> (0, 0)
  line L1 (0, 0) -> (0, 13)
  line L2 (0, 13) -> (-49, 13)
  line L3 (-49, 13) -> (-49, 0)
  line L4 (0, 0) -> (-8, 0)
  line L5 (-8, 0) -> (-8, 7.8)
  circle A0 centre (-8, 7.8) radius 2.5
  circle A1 centre (-41, 7.8) radius 2
  dimension "d42" = 8
  dimension "d43" = 7.8
  dimension "d44" = 5
  constraint coincident L0.end L1.start
  constraint perpendicular L1 L4
  constraint perpendicular L4 L5
  constraint coincident L5.end A0.centre
  measures "d42" distance of L0.end L4.end
  measures "d43" distance of L4.end L5.end
  measures "d44" diameter of A0
extrude "Wyciągnięcie proste11" cut sketch "Szkic15" against normal blind 2 contours A0
sketch "Szkic16" plane through (0, 0, 13) normal (0, 0, 1) x (-1, 0, 0)
  line L0 (-42, -29.9) -> (-47, -29.9)
  line L1 (-47, -29.9) -> (-47, -2)
  line L2 (-14.5, -2) -> (-7, -2)
  line L3 (-7, -2) -> (-7, -7)
  line L4 (-7, -7) -> (-2, -7)
  line L5 (-2, -7) -> (-2, -7.1)
  line L6 (-2, -7.1) -> (-2, -35)
  line L7 (-2, -35) -> (-42, -35)
  line L8 (-42, -35) -> (-42, -29.9)
  line L9 (-49, 0) -> (-49, -37)
  line L10 (-49, -37) -> (0, -37)
  line L11 (0, -37) -> (0, 0)
  line L12 (0, 0) -> (-49, 0)
  line L13 (0, 0) -> (-3.5928, 0)
  line L14 (-3.5928, 0) -> (-3.5928, -3.5)
  line L15 (-3.5928, -3.5) -> (0, -3.5)
  line L16 (0, -3.5) -> (0, 0)
  line L17 (-49, -37) -> (-45.5, -37)
  line L18 (-45.5, -37) -> (-45.5, -33.4072)
  line L19 (-45.5, -33.4072) -> (-49, -33.4072)
  line L20 (-49, -33.4072) -> (-49, -37)
  line L21 (-47, -2) -> (-14.5, -2)
  constraint horizontal L13
  constraint vertical L14
  constraint horizontal L15
  constraint vertical L16
  constraint coincident L11.end L12.start
  constraint horizontal L17
  constraint vertical L18
  constraint horizontal L19
  constraint vertical L20
  constraint coincident L9.end L10.start
hole "Otwór1" at (45.5, 33.4072, 13) at (3.5928, 3.5, 13) direction (0, 0, -1) diameter 1.623 depth 8 tip angle 118
thread "Gwint1" "ISO Metric profile 2.0 M2x0.4 M2x0.4 6H" major diameter 2.074 minor diameter 1.623 pitch 0.4 angle 60 resizes the face on face at (44.6888, 33.4275, 10.3333) on face at (3.6736, 2.6925, 10.3333)
fillet "Zaokrąglenie1" radius 1 4 edges at (0, 0, 6.5) (49, 0, 6.5) (0, 37, 6.5) (49, 37, 6.5)
sketch "Szkic17" plane through (0, 44, 0) normal (0, 1, 0) x (-1, 0, 0)
  circle A0 centre (-41, 7.8) radius 2
  circle A1 centre (-41, 7.8) radius 2
  circle A2 centre (-41, 7.8) radius 1
  line L0 (-41, 6.8) -> (-40.1339, 8.2998)
  line L1 (-41, 6.8) -> (-41.8661, 8.2998)
  line L2 (-41.8661, 8.2998) -> (-40.1339, 8.2998)
  constraint concentric A0 A1
  constraint concentric A1 A2
  constraint coincident A2 L0.start
  constraint coincident A2 L0.end
  constraint coincident A2 L1.end
  constraint horizontal L2
extrude "Wyciągnięcie proste12" cut sketch "Szkic17" against normal blind 3 contours L0 L1 L2
sketch "Szkic18" plane through (0, -7, 0) normal (0, -1, 0) x (1, 0, 0)
  circle A0 centre (8, 7.8) radius 2
  circle A1 centre (8, 7.8) radius 2
  circle A2 centre (8, 7.8) radius 1
  line L0 (8, 6.8) -> (8.8661, 8.2999)
  line L1 (8, 6.8) -> (7.1339, 8.2999)
  line L2 (7.1339, 8.2999) -> (8.8661, 8.2999)
  dimension "d77" = 2
  constraint concentric A0 A1
  constraint concentric A1 A2
  constraint coincident A2 L0.start
  constraint coincident A2 L0.end
  constraint coincident A2 L1.end
  constraint horizontal L2
  measures "d77" diameter of A2
extrude "Wyciągnięcie proste13" cut sketch "Szkic18" against normal blind 3 contours L0 L1 L2
sketch "Szkic19" plane through (0, 0, 0) normal (0, -1, 0) x (1, 0, 0)
  circle A0 centre (8, 7.8) radius 2
  circle A1 centre (41, 7.8) radius 2.5
  line L0 (48, 0) -> (48, 13)
  line L1 (48, 13) -> (1, 13)
  line L2 (1, 13) -> (1, 0)
  line L3 (1, 0) -> (48, 0)
  circle A2 centre (8, 7.8) radius 3.5
  dimension "d80" = 7
  constraint concentric A0 A2
  measures "d80" diameter of A2
extrude "Wyciągnięcie proste14" add sketch "Szkic19" along normal blind 0.5 contours A2
sketch "Szkic20" plane through (0, 37, 0) normal (0, 1, 0) x (-1, 0, 0)
  circle A0 centre (-8, 7.8) radius 2.5
  circle A1 centre (-41, 7.8) radius 2
  line L0 (-48, 13) -> (-48, 0)
  line L1 (-48, 0) -> (-1, 0)
  line L2 (-1, 0) -> (-1, 13)
  line L3 (-1, 13) -> (-48, 13)
  circle A2 centre (-41, 7.8) radius 3.5
  dimension "d83" = 7
  constraint concentric A1 A2
  measures "d83" diameter of A2
extrude "Wyciągnięcie proste15" add sketch "Szkic20" along normal blind 0.5 contours A2

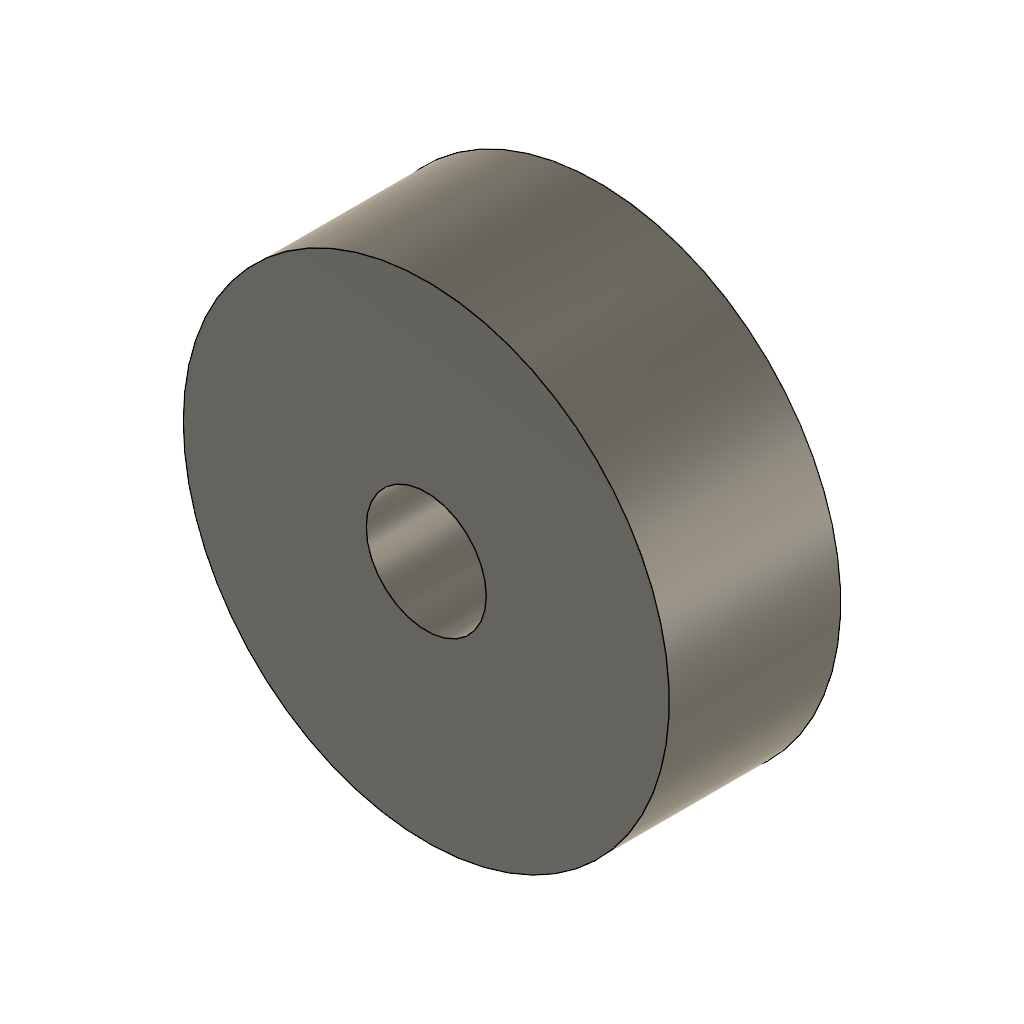
design "WheelType2"
part number: 2026-10-04-14-52-17-091
Autodesk Fusion 360 part; units mm, degrees
sketch "Szkic1" plane through (0, 0, 0) normal (0, 1, 0) x (1, 0, 0)
  circle A0 centre (0, 0) radius 2.1
  circle A1 centre (0, 0) radius 8.5
  dimension "d7" = 4.2
  dimension "d10" = 17
  measures "d7" diameter of A0
  measures "d10" diameter of A1
extrude "Wyciągnięcie proste1" add sketch "Szkic1" along normal blind 6

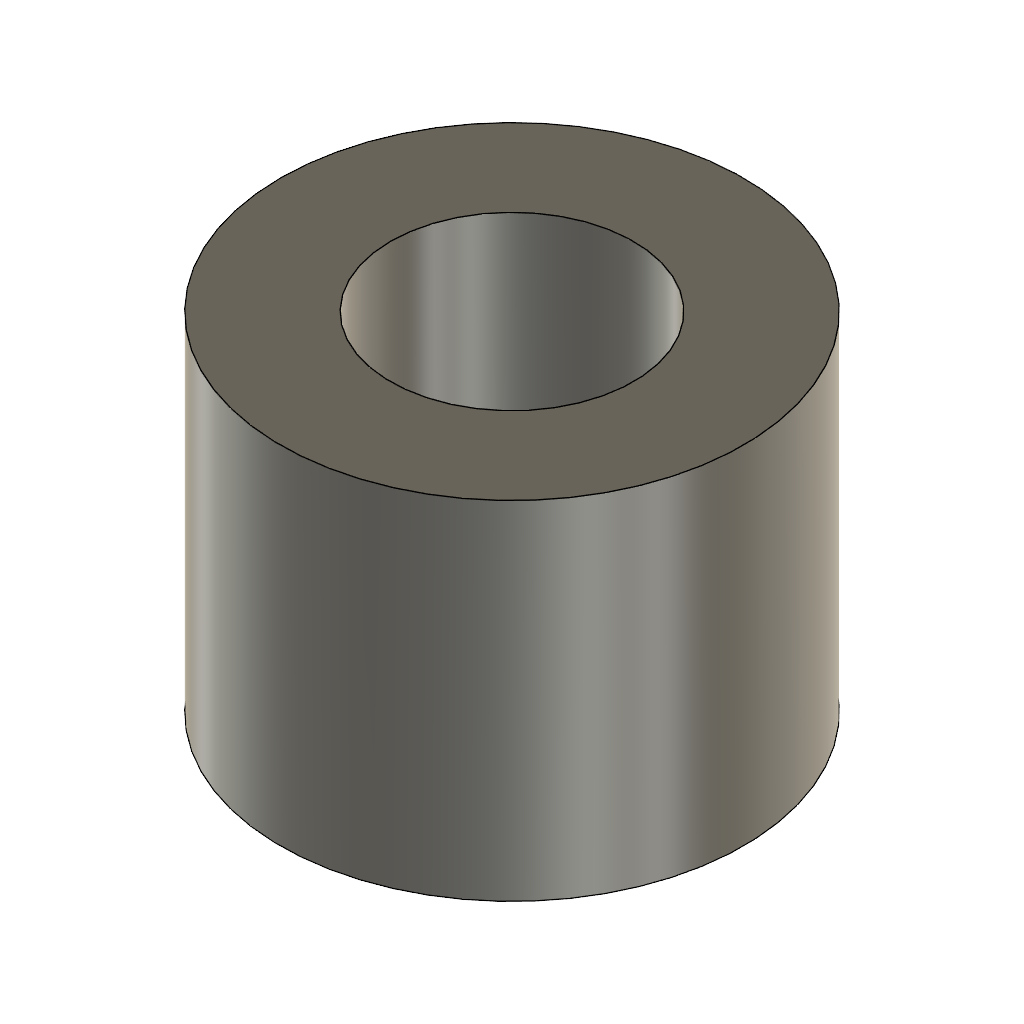
design "TensionWheel"
part number: 2026-10-11-19-17-43-800
Autodesk Fusion 360 part; units mm, degrees
sketch "Szkic1" plane through (0, 0, 0) normal (0, 0, 1) x (1, 0, 0)
  circle A0 centre (0, 0) radius 2.1
  circle A1 centre (0, 0) radius 4
  dimension "d1" = 4.2
  dimension "d5" = 8
  constraint coincident A0.centre A1.centre
  measures "d1" diameter of A0
  measures "d5" diameter of A1
extrude "Wyciągnięcie proste1" add sketch "Szkic1" along normal blind 6

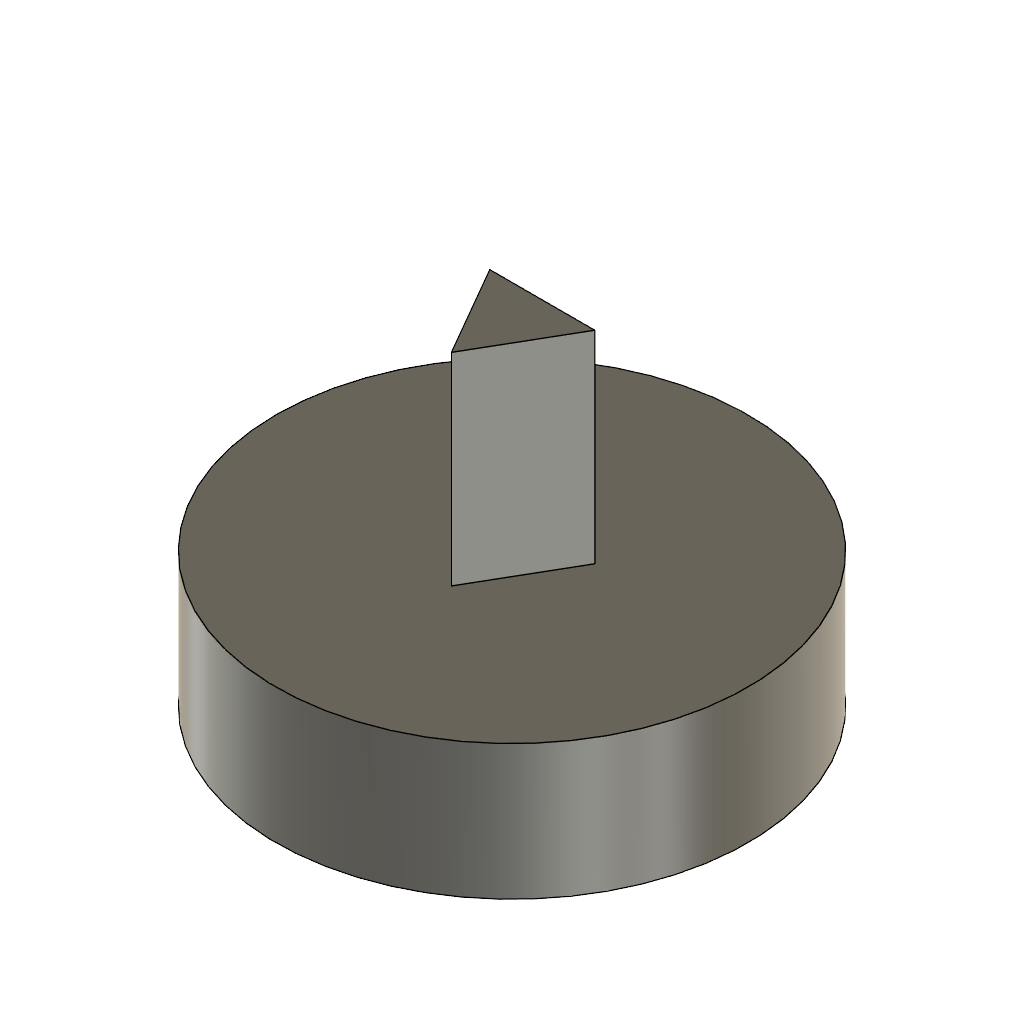
design "WheelCap"
part number: 2026-10-10-16-35-32-340
Autodesk Fusion 360 part; units mm, degrees
sketch "Szkic1" plane through (0, 0, 0) normal (0, 0, 1) x (1, 0, 0)
  circle A0 centre (0, 0) radius 3.5
  dimension "d7" = 7
  constraint coincident A0.centre origin
  measures "d7" diameter of A0
extrude "Wyciągnięcie proste1" add sketch "Szkic1" along normal blind 2
sketch "Szkic2" plane through (0, 0, 2) normal (0, 0, 1) x (-1, 0, 0)
  circle A0 centre (0, 0) radius 0.9
  line L0 (0, 0) -> (0, 0.9)
  line L1 (0, 0.9) -> (-0.7796, -0.4497)
  line L2 (0, 0.9) -> (0.7796, -0.4497)
  line L3 (0.7796, -0.4497) -> (-0.7796, -0.4497)
  circle A1 centre (0, 0) radius 3.5
  dimension "d4" = 1.8
  constraint coincident A0.centre L0.start
  constraint coincident A0 L0.end
  constraint vertical L0
  constraint coincident A0 L1.end
  constraint coincident A0 L2.end
  constraint perpendicular L0 L3
  measures "d4" diameter of A0
extrude "Wyciągnięcie proste2" add sketch "Szkic2" along normal blind 3 contours L1 L2 L3

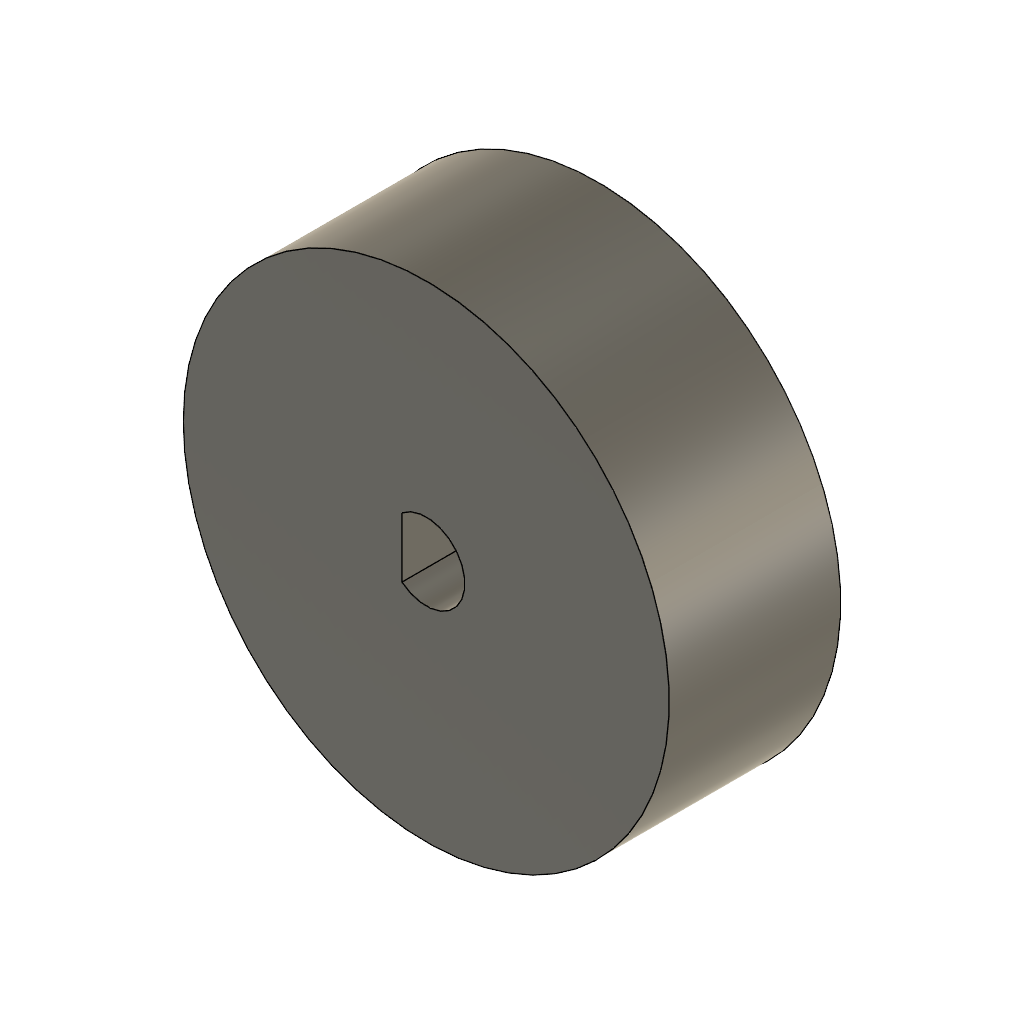
design "WheelType1"
part number: 2026-10-04-00-19-53-659
Autodesk Fusion 360 part; units mm, degrees
sketch "Szkic1" plane through (0, 0, 0) normal (0, 1, 0) x (1, 0, 0)
  line L0 (-0.85, -0.9) -> (-0.85, -1.0488)
  line L1 (-0.85, 1.0488) -> (-0.85, -0.9)
  arc A0 (-0.85, -1.0488) -> (-0.85, 1.0488) centre (0, 0) ccw
  circle A1 centre (0, 0) radius 8.5
  dimension "d5" = 2.7
  dimension "d9" = 17
  constraint coincident A0.centre A1.centre
  constraint parallel L0 L1
  measures "d5" diameter of A0
  measures "d9" diameter of A1
extrude "Wyciągnięcie proste1" add sketch "Szkic1" along normal blind 6

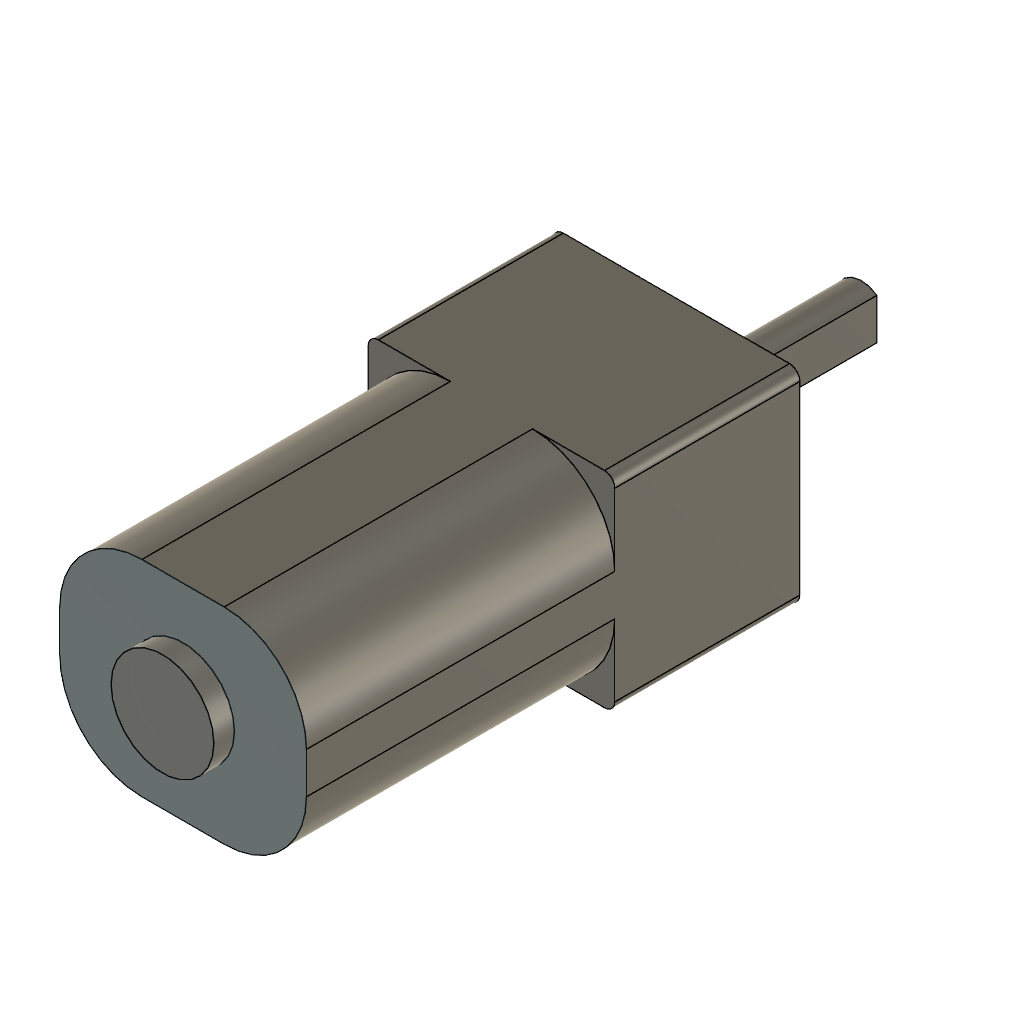
design "MiniMotor"
part number: 2026-09-30-19-01-18-395
Autodesk Fusion 360 part; units mm, degrees
sketch "Szkic1" plane through (0, 0, 0) normal (0, 1, 0) x (1, 0, 0)
  line L0 (4, 0) -> (8, 0)
  line L1 (12, -4) -> (12, -6)
  line L2 (8, -10) -> (4, -10)
  line L3 (0, -6) -> (0, -4)
  arc A0 (0, -6) -> (4, -10) centre (4, -6) ccw
  arc A1 (4, 0) -> (0, -4) centre (4, -4) ccw
  arc A2 (8, -10) -> (12, -6) centre (8, -6) ccw
  arc A3 (12, -4) -> (8, 0) centre (8, -4) ccw
  dimension "d1" = 4
  dimension "d2" = 4
  dimension "d3" = 4
  dimension "d4" = 4
  constraint horizontal L0
  constraint vertical L1
  constraint horizontal L2
  constraint vertical L3
  constraint tangent L3 A0
  constraint tangent L2 A0
  constraint tangent L0 A1
  constraint tangent L3 A1
  constraint tangent L1 A2
  constraint tangent L2 A2
  constraint tangent L0 A3
  constraint tangent L1 A3
  measures "d1" radius of A0
  measures "d2" radius of A1
  measures "d3" radius of A2
  measures "d4" radius of A3
extrude "Wyciągnięcie proste1" add sketch "Szkic1" along normal blind 15
sketch "Szkic2" plane through (0, 15, 0) normal (0, 1, 0) x (-1, 0, 0)
  arc A0 (-8, 10) -> (-12, 6) centre (-8, 6) ccw
  line L0 (-12, 6) -> (-12, 4)
  arc A1 (-12, 4) -> (-8, 0) centre (-8, 4) ccw
  line L1 (-8, 0) -> (-4, 0)
  arc A2 (-4, 0) -> (0, 4) centre (-4, 4) ccw
  line L2 (0, 4) -> (0, 6)
  arc A3 (0, 6) -> (-4, 10) centre (-4, 6) ccw
  line L3 (-4, 10) -> (-8, 10)
  line L4 (-12, 10) -> (0, 10)
  line L5 (0, 10) -> (0, 0)
  line L6 (0, 0) -> (-12, 0)
  line L7 (-12, 0) -> (-12, 10)
  constraint horizontal L4
  constraint vertical L5
  constraint horizontal L6
  constraint vertical L7
  constraint coincident L5.end L6.start
extrude "Wyciągnięcie proste2" add sketch "Szkic2" along normal blind 9
sketch "Szkic3" plane through (0, 24, 0) normal (0, 1, 0) x (-1, 0, 0)
  line L0 (-12, 0) -> (0, 0)
  line L1 (0, 0) -> (0, 10)
  line L2 (0, 10) -> (-12, 10)
  line L3 (-12, 10) -> (-12, 0)
  line L4 (-6.75, 5) -> (-6.75, 6)
  line L5 (-6.75, 5) -> (-6.75, 4)
  arc A0 (-6.75, 4) -> (-6.75, 6) centre (-6, 5) ccw
  circle A1 centre (-6, 5) radius 1.25
  constraint concentric A0 A1
extrude "Wyciągnięcie proste3" add sketch "Szkic3" along normal blind 9 contours L4 L5 A0 A1
sketch "Szkic4" plane through (0, 24, 0) normal (0, 1, 0) x (-1, 0, 0)
  arc A0 (-6.75, 4) -> (-6.75, 6) centre (-6, 5) ccw
  line L0 (-6.75, 4) -> (-6.75, 6)
  line L1 (-12, 0) -> (0, 0)
  line L2 (0, 0) -> (0, 10)
  line L3 (0, 10) -> (-12, 10)
  line L4 (-12, 10) -> (-12, 0)
  circle A1 centre (-6, 5) radius 1.5
  dimension "d11" = 3
  constraint concentric A0 A1
  measures "d11" diameter of A1
extrude "Wyciągnięcie proste4" add sketch "Szkic4" along normal blind 0.5 contours A1
sketch "Szkic5" plane through (0, 0, 0) normal (0, -1, 0) x (1, 0, 0)
  arc A0 (12, 6) -> (8, 10) centre (8, 6) ccw
  line L0 (8, 10) -> (4, 10)
  arc A1 (4, 10) -> (0, 6) centre (4, 6) ccw
  line L1 (0, 6) -> (0, 4)
  arc A2 (0, 4) -> (4, 0) centre (4, 4) ccw
  line L2 (4, 0) -> (8, 0)
  arc A3 (8, 0) -> (12, 4) centre (8, 4) ccw
  line L3 (12, 4) -> (12, 6)
  circle A4 centre (6, 5) radius 2.5
  dimension "d14" = 5
  measures "d14" diameter of A4
extrude "Wyciągnięcie proste5" add sketch "Szkic5" along normal blind 1 contours A4
sketch "Szkic6" plane through (0, 0, 0) normal (0, -1, 0) x (1, 0, 0)
  circle A0 centre (6, 5) radius 2.5
  arc A1 (12, 6) -> (8, 10) centre (8, 6) ccw
  line L0 (8, 10) -> (4, 10)
  arc A2 (4, 10) -> (0, 6) centre (4, 6) ccw
  line L1 (0, 6) -> (0, 4)
  arc A3 (0, 4) -> (4, 0) centre (4, 4) ccw
  line L2 (4, 0) -> (8, 0)
  arc A4 (8, 0) -> (12, 4) centre (8, 4) ccw
  line L3 (12, 4) -> (12, 6)
fillet "Zaokrąglenie1" radius 0.5 1 edges at (0, 19.5, 10)
fillet "Zaokrąglenie2" radius 0.5 1 edges at (12, 19.5, 10)
fillet "Zaokrąglenie3" radius 0.5 1 edges at (12, 19.5, 0)
fillet "Zaokrąglenie4" radius 0.5 1 edges at (0, 19.5, 0)

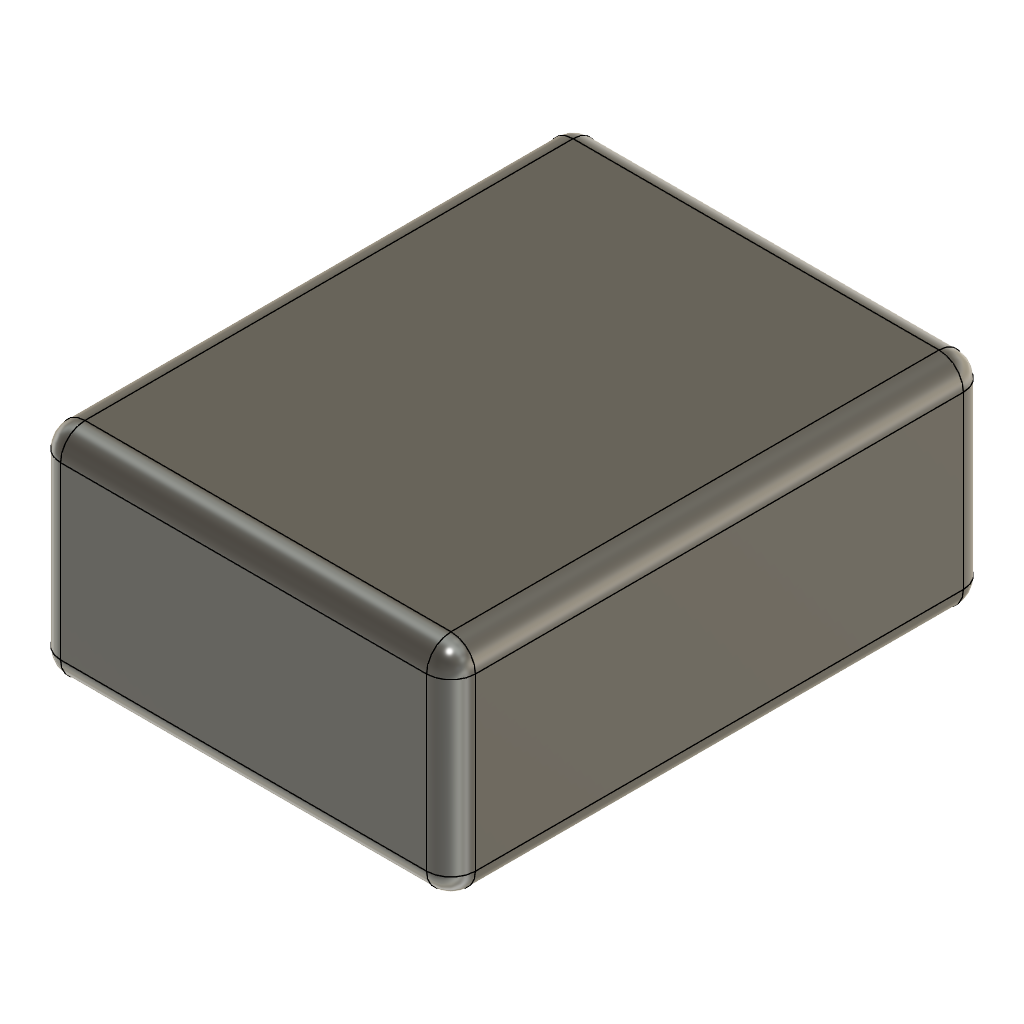
design "Battery"
part number: 2026-09-30-19-18-57-149
Autodesk Fusion 360 part; units mm, degrees
sketch "Szkic1" plane through (0, 0, 0) normal (0, 0, 1) x (1, 0, 0)
  line L0 (0, 0) -> (17, 0)
  line L1 (17, 0) -> (17, 22)
  line L2 (17, 22) -> (0, 22)
  line L3 (0, 22) -> (0, 0)
  constraint horizontal L0
  constraint vertical L1
  constraint horizontal L2
  constraint vertical L3
  constraint coincident L0.start L3.end
extrude "Wyciągnięcie proste1" add sketch "Szkic1" along normal blind 9
fillet "Zaokrąglenie1" radius 1 1 edges at (17, 0, 4.5)
fillet "Zaokrąglenie2" radius 1 1 edges at (0, 0, 4.5)
fillet "Zaokrąglenie3" radius 1 1 edges at (17, 22, 4.5)
fillet "Zaokrąglenie4" radius 1 1 edges at (0, 22, 4.5)
fillet "Zaokrąglenie5" radius 1 8 edges at (16.7071, 21.7071, 9) (8.5, 22, 9) (0.2929, 21.7071, 9) (0, 11, 9) (0.2929, 0.2929, 9) (8.5, 0, 9) (16.7071, 0.2929, 9) (17, 11, 9)
fillet "Zaokrąglenie6" radius 1 8 edges at (8.5, 22, 0) (0.2929, 21.7071, 0) (0, 11, 0) (0.2929, 0.2929, 0) (8.5, 0, 0) (16.7071, 0.2929, 0) (17, 11, 0) (16.7071, 21.7071, 0)
